Autodesk Fusion 360 part; units mm, degrees
(part 3 of 3)
ref_plane "WorkPlane3" through (-15.5, 0, 0) normal (1, 0, 0) x (0, 1, 0) in component "InnerFinger"
sketch "HW_M3x30_P1_0" plane through (-15.5, 0, 0) normal (1, 0, 0) x (0, 0, -1) in component "InnerFinger"
  circle A0 centre (-131.2077, -95.2377) radius 2.75
extrude "HW_M3x30_P1_0 (1)" add sketch "HW_M3x30_P1_0" along normal blind 3 separate body makes body 20 in component "InnerFinger"
ref_plane "WorkPlane4" through (-12.5, 0, 0) normal (1, 0, 0) x (0, 1, 0) in component "InnerFinger"
sketch "HW_M3x30_P1_1" plane through (-12.5, 0, 0) normal (1, 0, 0) x (0, 0, -1) in component "InnerFinger"
  circle A0 centre (-131.2077, -95.2377) radius 1.45
extrude "HW_M3x30_P1_1 (1)" add sketch "HW_M3x30_P1_1" along normal blind 30 bodies 20 in component "InnerFinger"
ref_plane "WorkPlane5" through (12.5, 0, 0) normal (1, 0, 0) x (0, 1, 0) in component "InnerFinger"
sketch "HW_M3x30_P1_2" plane through (12.5, 0, 0) normal (1, 0, 0) x (0, 0, -1) in component "InnerFinger"
  circle A0 centre (-131.2077, -95.2377) radius 3.2
extrude "HW_M3x30_P1_2 (1)" add sketch "HW_M3x30_P1_2" along normal blind 4 bodies 20 in component "InnerFinger"
sketch "HW_M3x30_P1_3" plane through (-12.5, 0, 0) normal (1, 0, 0) x (0, 0, -1) in component "InnerFinger"
  circle A0 centre (-131.2077, -95.2377) radius 3.5
extrude "HW_M3x30_P1_3 (1)" add sketch "HW_M3x30_P1_3" along normal blind 0.5 bodies 20 in component "InnerFinger"
ref_plane "WorkPlane6" through (12, 0, 0) normal (1, 0, 0) x (0, 1, 0) in component "InnerFinger"
sketch "HW_M3x30_P1_4" plane through (12, 0, 0) normal (1, 0, 0) x (0, 0, -1) in component "InnerFinger"
  circle A0 centre (-131.2077, -95.2377) radius 3.5
extrude "HW_M3x30_P1_4 (1)" add sketch "HW_M3x30_P1_4" along normal blind 0.5 bodies 20 in component "InnerFinger"
sketch "HW_M3x30_P2_0" plane through (-15.5, 0, 0) normal (1, 0, 0) x (0, 0, -1) in component "InnerFinger"
  circle A0 centre (-137.7227, -77.3367) radius 2.75
extrude "HW_M3x30_P2_0 (1)" add sketch "HW_M3x30_P2_0" along normal blind 3 separate body makes body 21 in component "InnerFinger"
sketch "HW_M3x30_P2_1" plane through (-12.5, 0, 0) normal (1, 0, 0) x (0, 0, -1) in component "InnerFinger"
  circle A0 centre (-137.7227, -77.3367) radius 1.45
extrude "HW_M3x30_P2_1 (1)" add sketch "HW_M3x30_P2_1" along normal blind 30 bodies 21 in component "InnerFinger"
sketch "HW_M3x30_P2_2" plane through (12.5, 0, 0) normal (1, 0, 0) x (0, 0, -1) in component "InnerFinger"
  circle A0 centre (-137.7227, -77.3367) radius 3.2
extrude "HW_M3x30_P2_2 (1)" add sketch "HW_M3x30_P2_2" along normal blind 4 bodies 21 in component "InnerFinger"
sketch "HW_M3x30_P2_3" plane through (-12.5, 0, 0) normal (1, 0, 0) x (0, 0, -1) in component "InnerFinger"
  circle A0 centre (-137.7227, -77.3367) radius 3.5
extrude "HW_M3x30_P2_3 (1)" add sketch "HW_M3x30_P2_3" along normal blind 0.5 bodies 21 in component "InnerFinger"
sketch "HW_M3x30_P2_4" plane through (12, 0, 0) normal (1, 0, 0) x (0, 0, -1) in component "InnerFinger"
  circle A0 centre (-137.7227, -77.3367) radius 3.5
extrude "HW_M3x30_P2_4 (1)" add sketch "HW_M3x30_P2_4" along normal blind 0.5 bodies 21 in component "InnerFinger"
ref_plane "WorkPlane2" through (25, 0, 0) normal (1, 0, 0) x (0, 1, 0) in component "Rod"
sketch "HW_M3x12_PinK_0" plane through (25, 0, 0) normal (1, 0, 0) x (0, 0, -1) in component "Rod"
  circle A0 centre (-55.2636, -29.6145) radius 2.75
extrude "HW_M3x12_PinK_0 (1)" add sketch "HW_M3x12_PinK_0" along normal blind 3 separate body makes body 22 in component "Rod"
ref_plane "WorkPlane3" through (13, 0, 0) normal (1, 0, 0) x (0, 1, 0) in component "Rod"
sketch "HW_M3x12_PinK_1" plane through (13, 0, 0) normal (1, 0, 0) x (0, 0, -1) in component "Rod"
  circle A0 centre (-55.2636, -29.6145) radius 1.45
extrude "HW_M3x12_PinK_1 (1)" add sketch "HW_M3x12_PinK_1" along normal blind 12 bodies 22 in component "Rod"
ref_plane "WorkPlane4" through (15, 0, 0) normal (1, 0, 0) x (0, 1, 0) in component "Rod"
sketch "HW_M3x12_PinK_2" plane through (15, 0, 0) normal (1, 0, 0) x (0, 0, -1) in component "Rod"
  circle A0 centre (-55.2636, -29.6145) radius 2.75
extrude "HW_M3x12_PinK_2 (1)" add sketch "HW_M3x12_PinK_2" along normal blind 4 bodies 22 in component "Rod"
ref_plane "WorkPlane5" through (24.5, 0, 0) normal (1, 0, 0) x (0, 1, 0) in component "Rod"
sketch "HW_M3x12_PinK_3" plane through (24.5, 0, 0) normal (1, 0, 0) x (0, 0, -1) in component "Rod"
  circle A0 centre (-55.2636, -29.6145) radius 3.5
extrude "HW_M3x12_PinK_3 (1)" add sketch "HW_M3x12_PinK_3" along normal blind 0.5 bodies 22 in component "Rod"
ref_plane "WorkPlane6" through (19, 0, 0) normal (1, 0, 0) x (0, 1, 0) in component "Rod"
sketch "HW_M3x12_PinK_4" plane through (19, 0, 0) normal (1, 0, 0) x (0, 0, -1) in component "Rod"
  circle A0 centre (-55.2636, -29.6145) radius 3.5
extrude "HW_M3x12_PinK_4 (1)" add sketch "HW_M3x12_PinK_4" along normal blind 0.5 bodies 22 in component "Rod"
ref_plane "WorkPlane2" through (11, 0, 0) normal (1, 0, 0) x (0, 1, 0) in component "Crank"
sketch "HW_M3x16_PinC_0" plane through (11, 0, 0) normal (1, 0, 0) x (0, 0, -1) in component "Crank"
  circle A0 centre (-11.5519, -29.5521) radius 2.75
extrude "HW_M3x16_PinC_0 (1)" add sketch "HW_M3x16_PinC_0" along normal blind 3 separate body makes body 23 in component "Crank"
ref_plane "WorkPlane3" through (14, 0, 0) normal (1, 0, 0) x (0, 1, 0) in component "Crank"
sketch "HW_M3x16_PinC_1" plane through (14, 0, 0) normal (1, 0, 0) x (0, 0, -1) in component "Crank"
  circle A0 centre (-11.5519, -29.5521) radius 1.45
extrude "HW_M3x16_PinC_1 (1)" add sketch "HW_M3x16_PinC_1" along normal blind 16 bodies 23 in component "Crank"
ref_plane "WorkPlane4" through (25, 0, 0) normal (1, 0, 0) x (0, 1, 0) in component "Crank"
sketch "HW_M3x16_PinC_2" plane through (25, 0, 0) normal (1, 0, 0) x (0, 0, -1) in component "Crank"
  circle A0 centre (-11.5519, -29.5521) radius 3.2
extrude "HW_M3x16_PinC_2 (1)" add sketch "HW_M3x16_PinC_2" along normal blind 4 bodies 23 in component "Crank"
ref_plane "WorkPlane5" through (24.5, 0, 0) normal (1, 0, 0) x (0, 1, 0) in component "Crank"
sketch "HW_M3x16_PinC_3" plane through (24.5, 0, 0) normal (1, 0, 0) x (0, 0, -1) in component "Crank"
  circle A0 centre (-11.5519, -29.5521) radius 3.5
extrude "HW_M3x16_PinC_3 (1)" add sketch "HW_M3x16_PinC_3" along normal blind 0.5 bodies 23 in component "Crank"
ref_plane "WorkPlane6" through (19, 0, 0) normal (1, 0, 0) x (0, 1, 0) in component "Crank"
sketch "HW_M3x16_PinC_4" plane through (19, 0, 0) normal (1, 0, 0) x (0, 0, -1) in component "Crank"
  circle A0 centre (-11.5519, -29.5521) radius 3.5
extrude "HW_M3x16_PinC_4 (1)" add sketch "HW_M3x16_PinC_4" along normal blind 0.5 bodies 23 in component "Crank"
ref_plane "WorkPlane10" through (-7.7, 0, 0) normal (1, 0, 0) x (0, 1, 0) in component "HousingBox"
ref_plane "WorkPlane11" through (-4.7, 0, 0) normal (1, 0, 0) x (0, 1, 0) in component "HousingBox"
ref_plane "WorkPlane12" through (3.5, 0, 0) normal (1, 0, 0) x (0, 1, 0) in component "HousingBox"
ref_plane "WorkPlane13" through (4, 0, 0) normal (1, 0, 0) x (0, 1, 0) in component "HousingBox"
ref_plane "WorkPlane22" through (0, 0, 40) normal (0, 0, 1) x (1, 0, 0) in component "Tower"
ref_plane "WorkPlane23" through (0, 0, 28) normal (0, 0, 1) x (1, 0, 0) in component "Tower"
ref_plane "WorkPlane24" through (0, 0, 29.6) normal (0, 0, 1) x (1, 0, 0) in component "Tower"
ref_plane "WorkPlane14" through (0, 0, 4) normal (0, 0, 1) x (1, 0, 0) in component "HousingBox"
ref_plane "WorkPlane15" through (0, 0, -8) normal (0, 0, 1) x (1, 0, 0) in component "HousingBox"
ref_plane "WorkPlane16" through (0, 0, -7.6) normal (0, 0, 1) x (1, 0, 0) in component "HousingBox"
ref_plane "WorkPlane6" through (0, 0, -9) normal (0, 0, 1) x (1, 0, 0) in component "SpacerB"
ref_plane "WorkPlane7" through (0, 0, -84) normal (0, 0, 1) x (1, 0, 0) in component "SpacerB"
ref_plane "WorkPlane4" through (0, 0, -79.7) normal (0, 0, 1) x (1, 0, 0) in component "CameraMount"
sketch "HW_M3x8_Camera0_0" plane through (0, 0, -79.7) normal (0, 0, 1) x (1, 0, 0) in component "CameraMount"
  circle A0 centre (100.36, 22.41) radius 2.75
extrude "HW_M3x8_Camera0_0 (1)" add sketch "HW_M3x8_Camera0_0" along normal blind 3 separate body makes body 24 in component "CameraMount"
ref_plane "WorkPlane5" through (0, 0, -76.7) normal (0, 0, 1) x (1, 0, 0) in component "CameraMount"
sketch "HW_M3x8_Camera0_1" plane through (0, 0, -76.7) normal (0, 0, 1) x (1, 0, 0) in component "CameraMount"
  circle A0 centre (100.36, 22.41) radius 1.45
extrude "HW_M3x8_Camera0_1 (1)" add sketch "HW_M3x8_Camera0_1" along normal blind 8 bodies 24 in component "CameraMount"
sketch "HW_M3x8_Camera1_0" plane through (0, 0, -79.7) normal (0, 0, 1) x (1, 0, 0) in component "CameraMount"
  circle A0 centre (100.36, -22.59) radius 2.75
extrude "HW_M3x8_Camera1_0 (1)" add sketch "HW_M3x8_Camera1_0" along normal blind 3 separate body makes body 25 in component "CameraMount"
sketch "HW_M3x8_Camera1_1" plane through (0, 0, -76.7) normal (0, 0, 1) x (1, 0, 0) in component "CameraMount"
  circle A0 centre (100.36, -22.59) radius 1.45
extrude "HW_M3x8_Camera1_1 (1)" add sketch "HW_M3x8_Camera1_1" along normal blind 8 bodies 25 in component "CameraMount"
ref_plane "WorkPlane7" through (0, -86.3377, 0) normal (0, 1, 0) x (0, 0, 1) in component "InnerFinger"
sketch "HW_M3x16_Pad0_0" plane through (0, -86.3377, 0) normal (0, 1, 0) x (1, 0, 0) in component "InnerFinger"
  circle A0 centre (0, -151.2077) radius 2.75
extrude "HW_M3x16_Pad0_0 (1)" add sketch "HW_M3x16_Pad0_0" along normal blind 3 separate body makes body 26 in component "InnerFinger"
ref_plane "WorkPlane8" through (0, -83.3377, 0) normal (0, 1, 0) x (0, 0, 1) in component "InnerFinger"
sketch "HW_M3x16_Pad0_1" plane through (0, -83.3377, 0) normal (0, 1, 0) x (1, 0, 0) in component "InnerFinger"
  circle A0 centre (0, -151.2077) radius 1.45
extrude "HW_M3x16_Pad0_1 (1)" add sketch "HW_M3x16_Pad0_1" along normal blind 16 bodies 26 in component "InnerFinger"
ref_plane "WorkPlane9" through (0, -71.3377, 0) normal (0, 1, 0) x (0, 0, 1) in component "InnerFinger"
sketch "HW_M3x16_Pad0_2" plane through (0, -71.3377, 0) normal (0, 1, 0) x (1, 0, 0) in component "InnerFinger"
  line L0 (2.75, -152.7954) -> (0, -154.3831)
  line L1 (0, -154.3831) -> (-2.75, -152.7954)
  line L2 (-2.75, -152.7954) -> (-2.75, -149.62)
  line L3 (-2.75, -149.62) -> (0, -148.0323)
  line L4 (0, -148.0323) -> (2.75, -149.62)
  line L5 (2.75, -149.62) -> (2.75, -152.7954)
extrude "HW_M3x16_Pad0_2 (1)" add sketch "HW_M3x16_Pad0_2" along normal blind 4 bodies 26 in component "InnerFinger"
sketch "HW_M3x16_Pad1_0" plane through (0, -86.3377, 0) normal (0, 1, 0) x (1, 0, 0) in component "InnerFinger"
  circle A0 centre (0, -165.2077) radius 2.75
extrude "HW_M3x16_Pad1_0 (1)" add sketch "HW_M3x16_Pad1_0" along normal blind 3 separate body makes body 27 in component "InnerFinger"
sketch "HW_M3x16_Pad1_1" plane through (0, -83.3377, 0) normal (0, 1, 0) x (1, 0, 0) in component "InnerFinger"
  circle A0 centre (0, -165.2077) radius 1.45
extrude "HW_M3x16_Pad1_1 (1)" add sketch "HW_M3x16_Pad1_1" along normal blind 16 bodies 27 in component "InnerFinger"
sketch "HW_M3x16_Pad1_2" plane through (0, -71.3377, 0) normal (0, 1, 0) x (1, 0, 0) in component "InnerFinger"
  line L0 (2.75, -166.7954) -> (0, -168.3831)
  line L1 (0, -168.3831) -> (-2.75, -166.7954)
  line L2 (-2.75, -166.7954) -> (-2.75, -163.62)
  line L3 (-2.75, -163.62) -> (0, -162.0323)
  line L4 (0, -162.0323) -> (2.75, -163.62)
  line L5 (2.75, -163.62) -> (2.75, -166.7954)
extrude "HW_M3x16_Pad1_2 (1)" add sketch "HW_M3x16_Pad1_2" along normal blind 4 bodies 27 in component "InnerFinger"
ref_plane "WorkPlane4" through (-4.8, 0, 0) normal (1, 0, 0) x (0, 1, 0) in component "Servo_D5545GS"
sketch "X03_cut_circle (3)" plane through (-4.8, 0, 0) normal (1, 0, 0) x (0, 0, -1) in component "Servo_D5545GS"
  circle A0 centre (-12.55, -28.7988) radius 2.25
extrude "X03_cut_circle (1)''" cut sketch "X03_cut_circle (3)" along normal blind 3.4 bodies 3 in component "Servo_D5545GS"
sketch "X04_cut_circle (2)" plane through (-4.8, 0, 0) normal (1, 0, 0) x (0, 0, -1) in component "Servo_D5545GS"
  circle A0 centre (-22.45, -28.7988) radius 2.25
extrude "X04_cut_circle (1)'" cut sketch "X04_cut_circle (2)" along normal blind 3.4 bodies 3 in component "Servo_D5545GS"
sketch "X05_cut_circle (4)" plane through (-4.8, 0, 0) normal (1, 0, 0) x (0, 0, -1) in component "Servo_D5545GS"
  circle A0 centre (-12.55, 19.8012) radius 2.25
extrude "X05_cut_circle (1)'''" cut sketch "X05_cut_circle (4)" along normal blind 3.4 bodies 3 in component "Servo_D5545GS"
sketch "X06_cut_circle (4)" plane through (-4.8, 0, 0) normal (1, 0, 0) x (0, 0, -1) in component "Servo_D5545GS"
  circle A0 centre (-22.45, 19.8012) radius 2.25
extrude "X06_cut_circle (1)'''" cut sketch "X06_cut_circle (4)" along normal blind 3.4 bodies 3 in component "Servo_D5545GS"
ref_plane "WorkPlane2" through (0, 0, -72.3) normal (0, 0, 1) x (1, 0, 0) in component "RealSense_D435i_Ref"
sketch "Z01_cut_circle (2)" plane through (0, 0, -72.3) normal (0, 0, 1) x (1, 0, 0) in component "RealSense_D435i_Ref"
  circle A0 centre (100.36, 22.41) radius 1.25
extrude "Z01_cut_circle (1)'" cut sketch "Z01_cut_circle (2)" along normal blind 5.1 bodies 15 in component "RealSense_D435i_Ref"
sketch "Z02_cut_circle (3)" plane through (0, 0, -72.3) normal (0, 0, 1) x (1, 0, 0) in component "RealSense_D435i_Ref"
  circle A0 centre (100.36, -22.59) radius 1.25
extrude "Z02_cut_circle (1)''" cut sketch "Z02_cut_circle (3)" along normal blind 5.1 bodies 15 in component "RealSense_D435i_Ref"
ref_plane "WorkPlane10" through (-7.6, 0, 0) normal (1, 0, 0) x (0, 1, 0) in component "InnerFinger"
sketch "X04_cut_rect" plane through (-7.6, 0, 0) normal (1, 0, 0) x (0, 0, -1) in component "InnerFinger"
  line L0 (-121.2077, -71.3377) -> (-121.2077, -69.2377)
  line L1 (-121.2077, -69.2377) -> (-181.2077, -69.2377)
  line L2 (-181.2077, -69.2377) -> (-181.2077, -71.3377)
  line L3 (-181.2077, -71.3377) -> (-121.2077, -71.3377)
extrude "X04_cut_rect (1)" cut sketch "X04_cut_rect" along normal blind 15.2 bodies 10 in component "InnerFinger"
ref_plane "WorkPlane17" through (4, 0, 0) normal (1, 0, 0) x (0, 1, 0) in component "HousingBox"
sketch "HW_M3x16_ServoEar0_0" plane through (4, 0, 0) normal (1, 0, 0) x (0, 0, -1) in component "HousingBox"
  circle A0 centre (-12.55, -28.7988) radius 2.75
extrude "HW_M3x16_ServoEar0_0 (1)" add sketch "HW_M3x16_ServoEar0_0" along normal blind 3 separate body makes body 28 in component "HousingBox"
ref_plane "WorkPlane18" through (3.5, 0, 0) normal (1, 0, 0) x (0, 1, 0) in component "HousingBox"
sketch "HW_M3x16_ServoEar0_1" plane through (3.5, 0, 0) normal (1, 0, 0) x (0, 0, -1) in component "HousingBox"
  circle A0 centre (-12.55, -28.7988) radius 3.5
extrude "HW_M3x16_ServoEar0_1 (1)" add sketch "HW_M3x16_ServoEar0_1" along normal blind 0.5 bodies 28 in component "HousingBox"
ref_plane "WorkPlane19" through (-12, 0, 0) normal (1, 0, 0) x (0, 1, 0) in component "HousingBox"
sketch "HW_M3x16_ServoEar0_2" plane through (-12, 0, 0) normal (1, 0, 0) x (0, 0, -1) in component "HousingBox"
  circle A0 centre (-12.55, -28.7988) radius 1.45
extrude "HW_M3x16_ServoEar0_2 (1)" add sketch "HW_M3x16_ServoEar0_2" along normal blind 16 bodies 28 in component "HousingBox"
ref_plane "WorkPlane20" through (-5.2, 0, 0) normal (1, 0, 0) x (0, 1, 0) in component "HousingBox"
sketch "HW_M3x16_ServoEar0_3" plane through (-5.2, 0, 0) normal (1, 0, 0) x (0, 0, -1) in component "HousingBox"
  circle A0 centre (-12.55, -28.7988) radius 3.5
extrude "HW_M3x16_ServoEar0_3 (1)" add sketch "HW_M3x16_ServoEar0_3" along normal blind 0.5 bodies 28 in component "HousingBox"
ref_plane "WorkPlane21" through (-9.2, 0, 0) normal (1, 0, 0) x (0, 1, 0) in component "HousingBox"
sketch "HW_M3x16_ServoEar0_4" plane through (-9.2, 0, 0) normal (1, 0, 0) x (0, 0, -1) in component "HousingBox"
  line L0 (-14.1377, -26.0488) -> (-15.7254, -28.7988)
  line L1 (-15.7254, -28.7988) -> (-14.1377, -31.5488)
  line L2 (-14.1377, -31.5488) -> (-10.9623, -31.5488)
  line L3 (-10.9623, -31.5488) -> (-9.3746, -28.7988)
  line L4 (-9.3746, -28.7988) -> (-10.9623, -26.0488)
  line L5 (-10.9623, -26.0488) -> (-14.1377, -26.0488)
extrude "HW_M3x16_ServoEar0_4 (1)" add sketch "HW_M3x16_ServoEar0_4" along normal blind 4 bodies 28 in component "HousingBox"
sketch "HW_M3x16_ServoEar1_0" plane through (4, 0, 0) normal (1, 0, 0) x (0, 0, -1) in component "HousingBox"
  circle A0 centre (-22.45, -28.7988) radius 2.75
extrude "HW_M3x16_ServoEar1_0 (1)" add sketch "HW_M3x16_ServoEar1_0" along normal blind 3 separate body makes body 29 in component "HousingBox"
sketch "HW_M3x16_ServoEar1_1" plane through (3.5, 0, 0) normal (1, 0, 0) x (0, 0, -1) in component "HousingBox"
  circle A0 centre (-22.45, -28.7988) radius 3.5
extrude "HW_M3x16_ServoEar1_1 (1)" add sketch "HW_M3x16_ServoEar1_1" along normal blind 0.5 bodies 29 in component "HousingBox"
sketch "HW_M3x16_ServoEar1_2" plane through (-12, 0, 0) normal (1, 0, 0) x (0, 0, -1) in component "HousingBox"
  circle A0 centre (-22.45, -28.7988) radius 1.45
extrude "HW_M3x16_ServoEar1_2 (1)" add sketch "HW_M3x16_ServoEar1_2" along normal blind 16 bodies 29 in component "HousingBox"
sketch "HW_M3x16_ServoEar1_3" plane through (-5.2, 0, 0) normal (1, 0, 0) x (0, 0, -1) in component "HousingBox"
  circle A0 centre (-22.45, -28.7988) radius 3.5
extrude "HW_M3x16_ServoEar1_3 (1)" add sketch "HW_M3x16_ServoEar1_3" along normal blind 0.5 bodies 29 in component "HousingBox"
sketch "HW_M3x16_ServoEar1_4" plane through (-9.2, 0, 0) normal (1, 0, 0) x (0, 0, -1) in component "HousingBox"
  line L0 (-24.0377, -26.0488) -> (-25.6254, -28.7988)
  line L1 (-25.6254, -28.7988) -> (-24.0377, -31.5488)
  line L2 (-24.0377, -31.5488) -> (-20.8623, -31.5488)
  line L3 (-20.8623, -31.5488) -> (-19.2746, -28.7988)
  line L4 (-19.2746, -28.7988) -> (-20.8623, -26.0488)
  line L5 (-20.8623, -26.0488) -> (-24.0377, -26.0488)
extrude "HW_M3x16_ServoEar1_4 (1)" add sketch "HW_M3x16_ServoEar1_4" along normal blind 4 bodies 29 in component "HousingBox"
sketch "HW_M3x16_ServoEar2_0" plane through (4, 0, 0) normal (1, 0, 0) x (0, 0, -1) in component "HousingBox"
  circle A0 centre (-12.55, 19.8012) radius 2.75
extrude "HW_M3x16_ServoEar2_0 (1)" add sketch "HW_M3x16_ServoEar2_0" along normal blind 3 separate body makes body 30 in component "HousingBox"
sketch "HW_M3x16_ServoEar2_1" plane through (3.5, 0, 0) normal (1, 0, 0) x (0, 0, -1) in component "HousingBox"
  circle A0 centre (-12.55, 19.8012) radius 3.5
extrude "HW_M3x16_ServoEar2_1 (1)" add sketch "HW_M3x16_ServoEar2_1" along normal blind 0.5 bodies 30 in component "HousingBox"
sketch "HW_M3x16_ServoEar2_2" plane through (-12, 0, 0) normal (1, 0, 0) x (0, 0, -1) in component "HousingBox"
  circle A0 centre (-12.55, 19.8012) radius 1.45
extrude "HW_M3x16_ServoEar2_2 (1)" add sketch "HW_M3x16_ServoEar2_2" along normal blind 16 bodies 30 in component "HousingBox"
sketch "HW_M3x16_ServoEar2_3" plane through (-5.2, 0, 0) normal (1, 0, 0) x (0, 0, -1) in component "HousingBox"
  circle A0 centre (-12.55, 19.8012) radius 3.5
extrude "HW_M3x16_ServoEar2_3 (1)" add sketch "HW_M3x16_ServoEar2_3" along normal blind 0.5 bodies 30 in component "HousingBox"
sketch "HW_M3x16_ServoEar2_4" plane through (-9.2, 0, 0) normal (1, 0, 0) x (0, 0, -1) in component "HousingBox"
  line L0 (-14.1377, 22.5512) -> (-15.7254, 19.8012)
  line L1 (-15.7254, 19.8012) -> (-14.1377, 17.0512)
  line L2 (-14.1377, 17.0512) -> (-10.9623, 17.0512)
  line L3 (-10.9623, 17.0512) -> (-9.3746, 19.8012)
  line L4 (-9.3746, 19.8012) -> (-10.9623, 22.5512)
  line L5 (-10.9623, 22.5512) -> (-14.1377, 22.5512)
extrude "HW_M3x16_ServoEar2_4 (1)" add sketch "HW_M3x16_ServoEar2_4" along normal blind 4 bodies 30 in component "HousingBox"
sketch "HW_M3x16_ServoEar3_0" plane through (4, 0, 0) normal (1, 0, 0) x (0, 0, -1) in component "HousingBox"
  circle A0 centre (-22.45, 19.8012) radius 2.75
extrude "HW_M3x16_ServoEar3_0 (1)" add sketch "HW_M3x16_ServoEar3_0" along normal blind 3 separate body makes body 31 in component "HousingBox"
sketch "HW_M3x16_ServoEar3_1" plane through (3.5, 0, 0) normal (1, 0, 0) x (0, 0, -1) in component "HousingBox"
  circle A0 centre (-22.45, 19.8012) radius 3.5
extrude "HW_M3x16_ServoEar3_1 (1)" add sketch "HW_M3x16_ServoEar3_1" along normal blind 0.5 bodies 31 in component "HousingBox"
sketch "HW_M3x16_ServoEar3_2" plane through (-12, 0, 0) normal (1, 0, 0) x (0, 0, -1) in component "HousingBox"
  circle A0 centre (-22.45, 19.8012) radius 1.45
extrude "HW_M3x16_ServoEar3_2 (1)" add sketch "HW_M3x16_ServoEar3_2" along normal blind 16 bodies 31 in component "HousingBox"
sketch "HW_M3x16_ServoEar3_3" plane through (-5.2, 0, 0) normal (1, 0, 0) x (0, 0, -1) in component "HousingBox"
  circle A0 centre (-22.45, 19.8012) radius 3.5
extrude "HW_M3x16_ServoEar3_3 (1)" add sketch "HW_M3x16_ServoEar3_3" along normal blind 0.5 bodies 31 in component "HousingBox"
sketch "HW_M3x16_ServoEar3_4" plane through (-9.2, 0, 0) normal (1, 0, 0) x (0, 0, -1) in component "HousingBox"
  line L0 (-24.0377, 22.5512) -> (-25.6254, 19.8012)
  line L1 (-25.6254, 19.8012) -> (-24.0377, 17.0512)
  line L2 (-24.0377, 17.0512) -> (-20.8623, 17.0512)
  line L3 (-20.8623, 17.0512) -> (-19.2746, 19.8012)
  line L4 (-19.2746, 19.8012) -> (-20.8623, 22.5512)
  line L5 (-20.8623, 22.5512) -> (-24.0377, 22.5512)
extrude "HW_M3x16_ServoEar3_4 (1)" add sketch "HW_M3x16_ServoEar3_4" along normal blind 4 bodies 31 in component "HousingBox"
ref_plane "WorkPlane25" through (0, 0, 40) normal (0, 0, 1) x (1, 0, 0) in component "Tower"
sketch "HW_M3x12_Tower0_0" plane through (0, 0, 40) normal (0, 0, 1) x (1, 0, 0) in component "Tower"
  circle A0 centre (-29, -31) radius 2.75
extrude "HW_M3x12_Tower0_0 (1)" add sketch "HW_M3x12_Tower0_0" along normal blind 3 separate body makes body 32 in component "Tower"
ref_plane "WorkPlane26" through (0, 0, 28) normal (0, 0, 1) x (1, 0, 0) in component "Tower"
sketch "HW_M3x12_Tower0_1" plane through (0, 0, 28) normal (0, 0, 1) x (1, 0, 0) in component "Tower"
  circle A0 centre (-29, -31) radius 1.45
extrude "HW_M3x12_Tower0_1 (1)" add sketch "HW_M3x12_Tower0_1" along normal blind 12 bodies 32 in component "Tower"
ref_plane "WorkPlane27" through (0, 0, 29.6) normal (0, 0, 1) x (1, 0, 0) in component "Tower"
sketch "HW_M3x12_Tower0_2" plane through (0, 0, 29.6) normal (0, 0, 1) x (1, 0, 0) in component "Tower"
  line L0 (-28.2808, -27.9071) -> (-31.3189, -28.8307)
  line L1 (-31.3189, -28.8307) -> (-32.0381, -31.9236)
  line L2 (-32.0381, -31.9236) -> (-29.7192, -34.0929)
  line L3 (-29.7192, -34.0929) -> (-26.6811, -33.1693)
  line L4 (-26.6811, -33.1693) -> (-25.9619, -30.0764)
  line L5 (-25.9619, -30.0764) -> (-28.2808, -27.9071)
extrude "HW_M3x12_Tower0_2 (1)" add sketch "HW_M3x12_Tower0_2" along normal blind 4 bodies 32 in component "Tower"
sketch "HW_M3x12_Tower1_0" plane through (0, 0, 40) normal (0, 0, 1) x (1, 0, 0) in component "Tower"
  circle A0 centre (-29, 31) radius 2.75
extrude "HW_M3x12_Tower1_0 (1)" add sketch "HW_M3x12_Tower1_0" along normal blind 3 separate body makes body 33 in component "Tower"
sketch "HW_M3x12_Tower1_1" plane through (0, 0, 28) normal (0, 0, 1) x (1, 0, 0) in component "Tower"
  circle A0 centre (-29, 31) radius 1.45
extrude "HW_M3x12_Tower1_1 (1)" add sketch "HW_M3x12_Tower1_1" along normal blind 12 bodies 33 in component "Tower"
sketch "HW_M3x12_Tower1_2" plane through (0, 0, 29.6) normal (0, 0, 1) x (1, 0, 0) in component "Tower"
  line L0 (-25.9619, 30.0764) -> (-26.6811, 33.1693)
  line L1 (-26.6811, 33.1693) -> (-29.7192, 34.0929)
  line L2 (-29.7192, 34.0929) -> (-32.0381, 31.9236)
  line L3 (-32.0381, 31.9236) -> (-31.3189, 28.8307)
  line L4 (-31.3189, 28.8307) -> (-28.2808, 27.9071)
  line L5 (-28.2808, 27.9071) -> (-25.9619, 30.0764)
extrude "HW_M3x12_Tower1_2 (1)" add sketch "HW_M3x12_Tower1_2" along normal blind 4 bodies 33 in component "Tower"
sketch "HW_M3x12_Tower2_0" plane through (0, 0, 40) normal (0, 0, 1) x (1, 0, 0) in component "Tower"
  circle A0 centre (27, 31) radius 2.75
extrude "HW_M3x12_Tower2_0 (1)" add sketch "HW_M3x12_Tower2_0" along normal blind 3 separate body makes body 34 in component "Tower"
sketch "HW_M3x12_Tower2_1" plane through (0, 0, 28) normal (0, 0, 1) x (1, 0, 0) in component "Tower"
  circle A0 centre (27, 31) radius 1.45
extrude "HW_M3x12_Tower2_1 (1)" add sketch "HW_M3x12_Tower2_1" along normal blind 12 bodies 34 in component "Tower"
sketch "HW_M3x12_Tower2_2" plane through (0, 0, 29.6) normal (0, 0, 1) x (1, 0, 0) in component "Tower"
  line L0 (26.3911, 27.8835) -> (29.3945, 28.9144)
  line L1 (29.3945, 28.9144) -> (30.0034, 32.0309)
  line L2 (30.0034, 32.0309) -> (27.6089, 34.1165)
  line L3 (27.6089, 34.1165) -> (24.6055, 33.0856)
  line L4 (24.6055, 33.0856) -> (23.9966, 29.9691)
  line L5 (23.9966, 29.9691) -> (26.3911, 27.8835)
extrude "HW_M3x12_Tower2_2 (1)" add sketch "HW_M3x12_Tower2_2" along normal blind 4 bodies 34 in component "Tower"
sketch "HW_M3x12_Tower3_0" plane through (0, 0, 40) normal (0, 0, 1) x (1, 0, 0) in component "Tower"
  circle A0 centre (27, -10) radius 2.75
extrude "HW_M3x12_Tower3_0 (1)" add sketch "HW_M3x12_Tower3_0" along normal blind 3 separate body makes body 35 in component "Tower"
sketch "HW_M3x12_Tower3_1" plane through (0, 0, 28) normal (0, 0, 1) x (1, 0, 0) in component "Tower"
  circle A0 centre (27, -10) radius 1.45
extrude "HW_M3x12_Tower3_1 (1)" add sketch "HW_M3x12_Tower3_1" along normal blind 12 bodies 35 in component "Tower"
sketch "HW_M3x12_Tower3_2" plane through (0, 0, 29.6) normal (0, 0, 1) x (1, 0, 0) in component "Tower"
  line L0 (23.8698, -10.5338) -> (25.8971, -12.9778)
  line L1 (25.8971, -12.9778) -> (29.0274, -12.444)
  line L2 (29.0274, -12.444) -> (30.1302, -9.4662)
  line L3 (30.1302, -9.4662) -> (28.1029, -7.0222)
  line L4 (28.1029, -7.0222) -> (24.9726, -7.556)
  line L5 (24.9726, -7.556) -> (23.8698, -10.5338)
extrude "HW_M3x12_Tower3_2 (1)" add sketch "HW_M3x12_Tower3_2" along normal blind 4 bodies 35 in component "Tower"
ref_plane "WorkPlane22" through (0, 0, 4) normal (0, 0, 1) x (1, 0, 0) in component "HousingBox"
sketch "HW_M3x12_Base0_0" plane through (0, 0, 4) normal (0, 0, 1) x (1, 0, 0) in component "HousingBox"
  circle A0 centre (26.8, 11.1) radius 2.75
extrude "HW_M3x12_Base0_0 (1)" add sketch "HW_M3x12_Base0_0" along normal blind 3 separate body makes body 36 in component "HousingBox"
ref_plane "WorkPlane23" through (0, 0, -8) normal (0, 0, 1) x (1, 0, 0) in component "HousingBox"
sketch "HW_M3x12_Base0_1" plane through (0, 0, -8) normal (0, 0, 1) x (1, 0, 0) in component "HousingBox"
  circle A0 centre (26.8, 11.1) radius 1.45
extrude "HW_M3x12_Base0_1 (1)" add sketch "HW_M3x12_Base0_1" along normal blind 12 bodies 36 in component "HousingBox"
ref_plane "WorkPlane24" through (0, 0, -7.6) normal (0, 0, 1) x (1, 0, 0) in component "HousingBox"
sketch "HW_M3x12_Base0_2" plane through (0, 0, -7.6) normal (0, 0, 1) x (1, 0, 0) in component "HousingBox"
  line L0 (28.7332, 13.6192) -> (25.5849, 14.0337)
  line L1 (25.5849, 14.0337) -> (23.6518, 11.5146)
  line L2 (23.6518, 11.5146) -> (24.8668, 8.5808)
  line L3 (24.8668, 8.5808) -> (28.0151, 8.1663)
  line L4 (28.0151, 8.1663) -> (29.9482, 10.6854)
  line L5 (29.9482, 10.6854) -> (28.7332, 13.6192)
extrude "HW_M3x12_Base0_2 (1)" add sketch "HW_M3x12_Base0_2" along normal blind 4 bodies 36 in component "HousingBox"
sketch "HW_M3x12_Base1_0" plane through (0, 0, 4) normal (0, 0, 1) x (1, 0, 0) in component "HousingBox"
  circle A0 centre (-11.1, 26.8) radius 2.75
extrude "HW_M3x12_Base1_0 (1)" add sketch "HW_M3x12_Base1_0" along normal blind 3 separate body makes body 37 in component "HousingBox"
sketch "HW_M3x12_Base1_1" plane through (0, 0, -8) normal (0, 0, 1) x (1, 0, 0) in component "HousingBox"
  circle A0 centre (-11.1, 26.8) radius 1.45
extrude "HW_M3x12_Base1_1 (1)" add sketch "HW_M3x12_Base1_1" along normal blind 12 bodies 37 in component "HousingBox"
sketch "HW_M3x12_Base1_2" plane through (0, 0, -7.6) normal (0, 0, 1) x (1, 0, 0) in component "HousingBox"
  line L0 (-13.6192, 28.7332) -> (-14.0337, 25.5849)
  line L1 (-14.0337, 25.5849) -> (-11.5146, 23.6518)
  line L2 (-11.5146, 23.6518) -> (-8.5808, 24.8668)
  line L3 (-8.5808, 24.8668) -> (-8.1663, 28.0151)
  line L4 (-8.1663, 28.0151) -> (-10.6854, 29.9482)
  line L5 (-10.6854, 29.9482) -> (-13.6192, 28.7332)
extrude "HW_M3x12_Base1_2 (1)" add sketch "HW_M3x12_Base1_2" along normal blind 4 bodies 37 in component "HousingBox"
sketch "HW_M3x12_Base2_0" plane through (0, 0, 4) normal (0, 0, 1) x (1, 0, 0) in component "HousingBox"
  circle A0 centre (-18, -28.5) radius 2.75
extrude "HW_M3x12_Base2_0 (1)" add sketch "HW_M3x12_Base2_0" along normal blind 3 separate body makes body 38 in component "HousingBox"
sketch "HW_M3x12_Base2_1" plane through (0, 0, -8) normal (0, 0, 1) x (1, 0, 0) in component "HousingBox"
  circle A0 centre (-18, -28.5) radius 1.45
extrude "HW_M3x12_Base2_1 (1)" add sketch "HW_M3x12_Base2_1" along normal blind 12 bodies 38 in component "HousingBox"
sketch "HW_M3x12_Base2_2" plane through (0, 0, -7.6) normal (0, 0, 1) x (1, 0, 0) in component "HousingBox"
  line L0 (-18.1261, -31.6729) -> (-15.3152, -30.1957)
  line L1 (-15.3152, -30.1957) -> (-15.1891, -27.0227)
  line L2 (-15.1891, -27.0227) -> (-17.8739, -25.3271)
  line L3 (-17.8739, -25.3271) -> (-20.6848, -26.8043)
  line L4 (-20.6848, -26.8043) -> (-20.8109, -29.9773)
  line L5 (-20.8109, -29.9773) -> (-18.1261, -31.6729)
extrude "HW_M3x12_Base2_2 (1)" add sketch "HW_M3x12_Base2_2" along normal blind 4 bodies 38 in component "HousingBox"
sketch "HW_M3x12_Base3_0" plane through (0, 0, 4) normal (0, 0, 1) x (1, 0, 0) in component "HousingBox"
  circle A0 centre (11.1, -26.8) radius 2.75
extrude "HW_M3x12_Base3_0 (1)" add sketch "HW_M3x12_Base3_0" along normal blind 3 separate body makes body 39 in component "HousingBox"
sketch "HW_M3x12_Base3_1" plane through (0, 0, -8) normal (0, 0, 1) x (1, 0, 0) in component "HousingBox"
  circle A0 centre (11.1, -26.8) radius 1.45
extrude "HW_M3x12_Base3_1 (1)" add sketch "HW_M3x12_Base3_1" along normal blind 12 bodies 39 in component "HousingBox"
sketch "HW_M3x12_Base3_2" plane through (0, 0, -7.6) normal (0, 0, 1) x (1, 0, 0) in component "HousingBox"
  line L0 (13.6192, -28.7332) -> (14.0337, -25.5849)
  line L1 (14.0337, -25.5849) -> (11.5146, -23.6518)
  line L2 (11.5146, -23.6518) -> (8.5808, -24.8668)
  line L3 (8.5808, -24.8668) -> (8.1663, -28.0151)
  line L4 (8.1663, -28.0151) -> (10.6854, -29.9482)
  line L5 (10.6854, -29.9482) -> (13.6192, -28.7332)
extrude "HW_M3x12_Base3_2 (1)" add sketch "HW_M3x12_Base3_2" along normal blind 4 bodies 39 in component "HousingBox"
ref_plane "WorkPlane3" through (0, 0, -72.3) normal (0, 0, 1) x (1, 0, 0) in component "RealSense_D435i_Ref"
sketch "Z03_cut_circle (5)" plane through (0, 0, -72.3) normal (0, 0, 1) x (1, 0, 0) in component "RealSense_D435i_Ref"
  circle A0 centre (100.36, 22.41) radius 1.5
extrude "Z03_cut_circle (1)''''" cut sketch "Z03_cut_circle (5)" along normal blind 5.1 bodies 15 in component "RealSense_D435i_Ref"
sketch "Z04_cut_circle (4)" plane through (0, 0, -72.3) normal (0, 0, 1) x (1, 0, 0) in component "RealSense_D435i_Ref"
  circle A0 centre (100.36, -22.59) radius 1.5
extrude "Z04_cut_circle (1)'''" cut sketch "Z04_cut_circle (4)" along normal blind 5.1 bodies 15 in component "RealSense_D435i_Ref"
ref_plane "WorkPlane11" through (11.5, 0, 0) normal (1, 0, 0) x (0, 1, 0) in component "InnerKnuckle"
sketch "X00_add_hull (5)" plane through (11.5, 0, 0) normal (1, 0, 0) x (0, 0, -1) in component "InnerKnuckle"
  line L0 (-96.896, -51.2707) -> (-57.2186, -17.6597)
  arc A0 (-57.2186, -17.6597) -> (-65.6214, -7.7403) centre (-61.42, -12.7) ccw
  line L1 (-65.6214, -7.7403) -> (-105.2988, -41.3514)
  arc A1 (-105.2988, -41.3514) -> (-96.896, -51.2707) centre (-101.0974, -46.3111) ccw
extrude "X00_add_hull (1)''''" add sketch "X00_add_hull (5)" along normal blind 7.5 separate body makes body 40 in component "InnerKnuckle"
ref_plane "WorkPlane12" through (-19, 0, 0) normal (1, 0, 0) x (0, 1, 0) in component "InnerKnuckle"
sketch "X01_add_hull (4)" plane through (-19, 0, 0) normal (1, 0, 0) x (0, 0, -1) in component "InnerKnuckle"
  line L0 (-96.896, -51.2707) -> (-57.2186, -17.6597)
  arc A0 (-57.2186, -17.6597) -> (-65.6214, -7.7403) centre (-61.42, -12.7) ccw
  line L1 (-65.6214, -7.7403) -> (-105.2988, -41.3514)
  arc A1 (-105.2988, -41.3514) -> (-96.896, -51.2707) centre (-101.0974, -46.3111) ccw
extrude "X01_add_hull (1)'''" add sketch "X01_add_hull (4)" along normal blind 7.5 bodies 40 makes body 41 in component "InnerKnuckle"
sketch "X02_add_hull" plane through (11.5, 0, 0) normal (1, 0, 0) x (0, 0, -1) in component "InnerKnuckle"
  line L0 (-49.9988, -28.0234) -> (-55.1979, -10.8196)
  arc A0 (-55.1979, -10.8196) -> (-67.3951, -15.259) centre (-61.42, -12.7) ccw
  line L1 (-67.3951, -15.259) -> (-60.3195, -31.7798)
  arc A1 (-60.3195, -31.7798) -> (-49.9988, -28.0234) centre (-55.2636, -29.6145) ccw
extrude "X02_add_hull (1)" add sketch "X02_add_hull" along normal blind 7.5 bodies 40 41 in component "InnerKnuckle"
sketch "X03_add_hull" plane through (-19, 0, 0) normal (1, 0, 0) x (0, 0, -1) in component "InnerKnuckle"
  line L0 (-95.37, -49.978) -> (-89.2658, -44.8071)
  arc A0 (-89.2658, -44.8071) -> (-97.6685, -34.8877) centre (-93.4671, -39.8474) ccw
  line L1 (-97.6685, -34.8877) -> (-103.7727, -40.0587)
  arc A1 (-103.7727, -40.0587) -> (-95.37, -49.978) centre (-99.5714, -45.0183) ccw
extrude "X03_add_hull (1)" add sketch "X03_add_hull" along normal blind 38 bodies 40 41 in component "InnerKnuckle"
ref_plane "WorkPlane13" through (-12, 0, 0) normal (1, 0, 0) x (0, 1, 0) in component "InnerKnuckle"
sketch "X04_add_hull" plane through (-12, 0, 0) normal (1, 0, 0) x (0, 0, -1) in component "InnerKnuckle"
  line L0 (-133.5213, -82.2963) -> (-89.2658, -44.8071)
  arc A0 (-89.2658, -44.8071) -> (-97.6685, -34.8877) centre (-93.4671, -39.8474) ccw
  line L1 (-97.6685, -34.8877) -> (-141.9241, -72.377)
  arc A1 (-141.9241, -72.377) -> (-133.5213, -82.2963) centre (-137.7227, -77.3367) ccw
extrude "X04_add_hull (1)" add sketch "X04_add_hull" along normal blind 24 bodies 40 in component "InnerKnuckle"
ref_plane "WorkPlane14" through (-7.75, 0, 0) normal (1, 0, 0) x (0, 1, 0) in component "InnerKnuckle"
sketch "X05_cut_hull" plane through (-7.75, 0, 0) normal (1, 0, 0) x (0, 0, -1) in component "InnerKnuckle"
  line L0 (-132.0455, -83.3914) -> (-124.776, -76.5752)
  arc A0 (-124.776, -76.5752) -> (-134.8501, -64.6898) centre (-130.1112, -70.8852) ccw
  line L1 (-134.8501, -64.6898) -> (-142.7653, -70.7441)
  arc A1 (-142.7653, -70.7441) -> (-132.0455, -83.3914) centre (-137.7227, -77.3367) ccw
extrude "X05_cut_hull (1)" cut sketch "X05_cut_hull" along normal blind 15.5 bodies 40 in component "InnerKnuckle"
sketch "X06_cut_circle (5)" plane through (-19, 0, 0) normal (1, 0, 0) x (0, 0, -1) in component "InnerKnuckle"
  circle A0 centre (-61.42, -12.7) radius 1.65
extrude "X06_cut_circle (1)''''" cut sketch "X06_cut_circle (5)" along normal blind 38 bodies 40 in component "InnerKnuckle"
sketch "X07_cut_circle (5)" plane through (-12, 0, 0) normal (1, 0, 0) x (0, 0, -1) in component "InnerKnuckle"
  circle A0 centre (-137.7227, -77.3367) radius 1.65
extrude "X07_cut_circle (1)''''" cut sketch "X07_cut_circle (5)" along normal blind 24 bodies 40 in component "InnerKnuckle"
sketch "X08_cut_circle (3)" plane through (11.5, 0, 0) normal (1, 0, 0) x (0, 0, -1) in component "InnerKnuckle"
  circle A0 centre (-55.2636, -29.6145) radius 1.7
extrude "X08_cut_circle (1)''" cut sketch "X08_cut_circle (3)" along normal blind 7.5 bodies 40 in component "InnerKnuckle"
ref_plane "WorkPlane15" through (14.8, 0, 0) normal (1, 0, 0) x (0, 1, 0) in component "InnerKnuckle"
sketch "X09_cut_hex" plane through (14.8, 0, 0) normal (1, 0, 0) x (0, 0, -1) in component "InnerKnuckle"
  line L0 (-56.9091, -26.7645) -> (-58.5545, -29.6145)
  line L1 (-58.5545, -29.6145) -> (-56.9091, -32.4645)
  line L2 (-56.9091, -32.4645) -> (-53.6182, -32.4645)
  line L3 (-53.6182, -32.4645) -> (-51.9727, -29.6145)
  line L4 (-51.9727, -29.6145) -> (-53.6182, -26.7645)
  line L5 (-53.6182, -26.7645) -> (-56.9091, -26.7645)
extrude "X09_cut_hex (1)" cut sketch "X09_cut_hex" along normal blind 4.2 bodies 40 in component "InnerKnuckle"
ref_plane "WorkPlane8" through (0, 0, -14) normal (0, 0, 1) x (1, 0, 0) in component "SpacerB"
sketch "Z40_cut_circle" plane through (0, 0, -14) normal (0, 0, 1) x (1, 0, 0) in component "SpacerB"
  circle A0 centre (23.097, -9.5671) radius 5.5
extrude "Z40_cut_circle (1)" cut sketch "Z40_cut_circle" along normal blind 5.1 bodies 12 in component "SpacerB"
sketch "Z41_cut_circle" plane through (0, 0, -14) normal (0, 0, 1) x (1, 0, 0) in component "SpacerB"
  circle A0 centre (9.5671, 23.097) radius 5.5
extrude "Z41_cut_circle (1)" cut sketch "Z41_cut_circle" along normal blind 5.1 bodies 12 in component "SpacerB"
sketch "Z42_cut_circle" plane through (0, 0, -14) normal (0, 0, 1) x (1, 0, 0) in component "SpacerB"
  circle A0 centre (-23.097, 9.5671) radius 5.5
extrude "Z42_cut_circle (1)" cut sketch "Z42_cut_circle" along normal blind 5.1 bodies 12 in component "SpacerB"
sketch "Z43_cut_circle" plane through (0, 0, -14) normal (0, 0, 1) x (1, 0, 0) in component "SpacerB"
  circle A0 centre (-9.5671, -23.097) radius 5.5
extrude "Z43_cut_circle (1)" cut sketch "Z43_cut_circle" along normal blind 5.1 bodies 12 in component "SpacerB"
ref_plane "WorkPlane28" through (-22.5, 0, 0) normal (1, 0, 0) x (0, 1, 0) in component "Tower"
sketch "HW_M3x50_PivotI_L_0" plane through (-22.5, 0, 0) normal (1, 0, 0) x (0, 0, -1) in component "Tower"
  circle A0 centre (-61.42, -12.7) radius 2.75
extrude "HW_M3x50_PivotI_L_0 (1)" add sketch "HW_M3x50_PivotI_L_0" along normal blind 3 separate body makes body 42 in component "Tower"
ref_plane "WorkPlane29" through (-19.5, 0, 0) normal (1, 0, 0) x (0, 1, 0) in component "Tower"
sketch "HW_M3x50_PivotI_L_1" plane through (-19.5, 0, 0) normal (1, 0, 0) x (0, 0, -1) in component "Tower"
  circle A0 centre (-61.42, -12.7) radius 1.45
extrude "HW_M3x50_PivotI_L_1 (1)" add sketch "HW_M3x50_PivotI_L_1" along normal blind 50 bodies 42 in component "Tower"
ref_plane "WorkPlane30" through (19.5, 0, 0) normal (1, 0, 0) x (0, 1, 0) in component "Tower"
sketch "HW_M3x50_PivotI_L_2" plane through (19.5, 0, 0) normal (1, 0, 0) x (0, 0, -1) in component "Tower"
  circle A0 centre (-61.42, -12.7) radius 3.2
extrude "HW_M3x50_PivotI_L_2 (1)" add sketch "HW_M3x50_PivotI_L_2" along normal blind 4 bodies 42 in component "Tower"
sketch "HW_M3x50_PivotI_L_3" plane through (-19.5, 0, 0) normal (1, 0, 0) x (0, 0, -1) in component "Tower"
  circle A0 centre (-61.42, -12.7) radius 3.5
extrude "HW_M3x50_PivotI_L_3 (1)" add sketch "HW_M3x50_PivotI_L_3" along normal blind 0.5 bodies 42 in component "Tower"
ref_plane "WorkPlane31" through (19, 0, 0) normal (1, 0, 0) x (0, 1, 0) in component "Tower"
sketch "HW_M3x50_PivotI_L_4" plane through (19, 0, 0) normal (1, 0, 0) x (0, 0, -1) in component "Tower"
  circle A0 centre (-61.42, -12.7) radius 3.5
extrude "HW_M3x50_PivotI_L_4 (1)" add sketch "HW_M3x50_PivotI_L_4" along normal blind 0.5 bodies 42 in component "Tower"
ref_plane "WorkPlane32" through (-11.5, 0, 0) normal (1, 0, 0) x (0, 1, 0) in component "Tower"
sketch "HW_M3x50_PivotI_L_5" plane through (-11.5, 0, 0) normal (1, 0, 0) x (0, 0, -1) in component "Tower"
  circle A0 centre (-61.42, -12.7) radius 3.5
extrude "HW_M3x50_PivotI_L_5 (1)" add sketch "HW_M3x50_PivotI_L_5" along normal blind 0.5 bodies 42 in component "Tower"
ref_plane "WorkPlane33" through (11, 0, 0) normal (1, 0, 0) x (0, 1, 0) in component "Tower"
sketch "HW_M3x50_PivotI_L_6" plane through (11, 0, 0) normal (1, 0, 0) x (0, 0, -1) in component "Tower"
  circle A0 centre (-61.42, -12.7) radius 3.5
extrude "HW_M3x50_PivotI_L_6 (1)" add sketch "HW_M3x50_PivotI_L_6" along normal blind 0.5 bodies 42 in component "Tower"
sketch "HW_M3x50_PivotI_R_0" plane through (19.5, 0, 0) normal (1, 0, 0) x (0, 0, -1) in component "Tower"
  circle A0 centre (-61.42, 12.7) radius 2.75
extrude "HW_M3x50_PivotI_R_0 (1)" add sketch "HW_M3x50_PivotI_R_0" along normal blind 3 separate body makes body 43 in component "Tower"
ref_plane "WorkPlane34" through (-30.5, 0, 0) normal (1, 0, 0) x (0, 1, 0) in component "Tower"
sketch "HW_M3x50_PivotI_R_1" plane through (-30.5, 0, 0) normal (1, 0, 0) x (0, 0, -1) in component "Tower"
  circle A0 centre (-61.42, 12.7) radius 1.45
extrude "HW_M3x50_PivotI_R_1 (1)" add sketch "HW_M3x50_PivotI_R_1" along normal blind 50 bodies 43 in component "Tower"
ref_plane "WorkPlane35" through (-23.5, 0, 0) normal (1, 0, 0) x (0, 1, 0) in component "Tower"
sketch "HW_M3x50_PivotI_R_2" plane through (-23.5, 0, 0) normal (1, 0, 0) x (0, 0, -1) in component "Tower"
  circle A0 centre (-61.42, 12.7) radius 3.2
extrude "HW_M3x50_PivotI_R_2 (1)" add sketch "HW_M3x50_PivotI_R_2" along normal blind 4 bodies 43 in component "Tower"
sketch "HW_M3x50_PivotI_R_3" plane through (19, 0, 0) normal (1, 0, 0) x (0, 0, -1) in component "Tower"
  circle A0 centre (-61.42, 12.7) radius 3.5
extrude "HW_M3x50_PivotI_R_3 (1)" add sketch "HW_M3x50_PivotI_R_3" along normal blind 0.5 bodies 43 in component "Tower"
sketch "HW_M3x50_PivotI_R_4" plane through (-19.5, 0, 0) normal (1, 0, 0) x (0, 0, -1) in component "Tower"
  circle A0 centre (-61.42, 12.7) radius 3.5
extrude "HW_M3x50_PivotI_R_4 (1)" add sketch "HW_M3x50_PivotI_R_4" along normal blind 0.5 bodies 43 in component "Tower"
sketch "HW_M3x50_PivotI_R_5" plane through (11, 0, 0) normal (1, 0, 0) x (0, 0, -1) in component "Tower"
  circle A0 centre (-61.42, 12.7) radius 3.5
extrude "HW_M3x50_PivotI_R_5 (1)" add sketch "HW_M3x50_PivotI_R_5" along normal blind 0.5 bodies 43 in component "Tower"
sketch "HW_M3x50_PivotI_R_6" plane through (-11.5, 0, 0) normal (1, 0, 0) x (0, 0, -1) in component "Tower"
  circle A0 centre (-61.42, 12.7) radius 3.5
extrude "HW_M3x50_PivotI_R_6 (1)" add sketch "HW_M3x50_PivotI_R_6" along normal blind 0.5 bodies 43 in component "Tower"
sketch "HW_M6x70_Flange0_0" plane through (0, 0, -14) normal (0, 0, 1) x (1, 0, 0) in component "SpacerB"
  circle A0 centre (23.097, -9.5671) radius 5
extrude "HW_M6x70_Flange0_0 (1)" add sketch "HW_M6x70_Flange0_0" along normal blind 6 separate body makes body 44 in component "SpacerB"
ref_plane "WorkPlane9" through (0, 0, -84) normal (0, 0, 1) x (1, 0, 0) in component "SpacerB"
sketch "HW_M6x70_Flange0_1" plane through (0, 0, -84) normal (0, 0, 1) x (1, 0, 0) in component "SpacerB"
  circle A0 centre (23.097, -9.5671) radius 2.95
extrude "HW_M6x70_Flange0_1 (1)" add sketch "HW_M6x70_Flange0_1" along normal blind 70 bodies 44 in component "SpacerB"
sketch "HW_M6x70_Flange1_0" plane through (0, 0, -14) normal (0, 0, 1) x (1, 0, 0) in component "SpacerB"
  circle A0 centre (9.5671, 23.097) radius 5
extrude "HW_M6x70_Flange1_0 (1)" add sketch "HW_M6x70_Flange1_0" along normal blind 6 separate body makes body 45 in component "SpacerB"
sketch "HW_M6x70_Flange1_1" plane through (0, 0, -84) normal (0, 0, 1) x (1, 0, 0) in component "SpacerB"
  circle A0 centre (9.5671, 23.097) radius 2.95
extrude "HW_M6x70_Flange1_1 (1)" add sketch "HW_M6x70_Flange1_1" along normal blind 70 bodies 45 in component "SpacerB"
sketch "HW_M6x70_Flange2_0" plane through (0, 0, -14) normal (0, 0, 1) x (1, 0, 0) in component "SpacerB"
  circle A0 centre (-23.097, 9.5671) radius 5
extrude "HW_M6x70_Flange2_0 (1)" add sketch "HW_M6x70_Flange2_0" along normal blind 6 separate body makes body 46 in component "SpacerB"
sketch "HW_M6x70_Flange2_1" plane through (0, 0, -84) normal (0, 0, 1) x (1, 0, 0) in component "SpacerB"
  circle A0 centre (-23.097, 9.5671) radius 2.95
extrude "HW_M6x70_Flange2_1 (1)" add sketch "HW_M6x70_Flange2_1" along normal blind 70 bodies 46 in component "SpacerB"
sketch "HW_M6x70_Flange3_0" plane through (0, 0, -14) normal (0, 0, 1) x (1, 0, 0) in component "SpacerB"
  circle A0 centre (-9.5671, -23.097) radius 5
extrude "HW_M6x70_Flange3_0 (1)" add sketch "HW_M6x70_Flange3_0" along normal blind 6 separate body makes body 47 in component "SpacerB"
sketch "HW_M6x70_Flange3_1" plane through (0, 0, -84) normal (0, 0, 1) x (1, 0, 0) in component "SpacerB"
  circle A0 centre (-9.5671, -23.097) radius 2.95
extrude "HW_M6x70_Flange3_1 (1)" add sketch "HW_M6x70_Flange3_1" along normal blind 70 bodies 47 in component "SpacerB"
component "Tower" placed x (1, 0, 0) y (0, 1, 0) z (0, 0, 1) at (0, 0, 0)
component "HousingBox" placed x (1, 0, 0) y (0, 1, 0) z (0, 0, 1) at (0, 0, 0)
component "Servo_D5545GS" placed x (1, 0, 0) y (0, 1, 0) z (0, 0, 1) at (0, 0, 0)
component "ServoHorn_Ref" placed x (1, 0, 0) y (0, 1, 0) z (0, 0, 1) at (0, 0, 0)
component "Crank" placed x (1, 0, 0) y (0, 1, 0) z (0, 0, 1) at (0, 0, 0)
component "Rod" placed x (1, 0, 0) y (0, 1, 0) z (0, 0, 1) at (0, 0, 0)
component "OuterKnuckle_L" placed x (1, 0, 0) y (0, 1, 0) z (0, 0, 1) at (0, 0, 0)
component "OuterKnuckle_R" placed x (-1, 0, 0) y (0, -1, 0) z (0, 0, 1) at (0, 0, 0)
component "OuterFinger" placed x (1, 0, 0) y (0, 1, 0) z (0, 0, 1) at (0, 0, 0)
component "InnerKnuckle" placed x (1, 0, 0) y (0, 1, 0) z (0, 0, 1) at (0, 0, 0)
component "InnerFinger" placed x (1, 0, 0) y (0, 1, 0) z (0, 0, 1) at (0, 0, 0)
component "Fingertip" placed x (1, 0, 0) y (0, 1, 0) z (0, 0, 1) at (0, 0, 0)
component "SpacerB" placed x (1, 0, 0) y (0, 1, 0) z (0, 0, 1) at (0, 0, 0)
component "SpacerA" placed x (1, 0, 0) y (0, 1, 0) z (0, 0, 1) at (0, 0, 0)
component "CameraMount" placed x (1, 0, 0) y (0, 1, 0) z (0, 0, 1) at (0, 0, 0)
component "RealSense_D435i_Ref" placed x (1, 0, 0) y (0, 1, 0) z (0, 0, 1) at (0, 0, 0)
component "OuterFinger" placed x (-1, 0, 0) y (0, -1, 0) z (0, 0, 1) at (0, 0, 0)
component "InnerKnuckle" placed x (-1, 0, 0) y (0, -1, 0) z (0, 0, 1) at (0, 0, 0)
component "InnerFinger" placed x (-1, 0, 0) y (0, -1, 0) z (0, 0, 1) at (0, 0, 0)
component "Fingertip" placed x (-1, 0, 0) y (0, -1, 0) z (0, 0, 1) at (0, 0, 0)
named bodies: "Tower", "HousingBox", "Servo_D5545GS", "ServoHorn_Ref", "Crank", "Rod", "OuterKnuckle_L", "OuterKnuckle_R", "OuterFinger", "InnerFinger", "Fingertip", "SpacerB", "SpacerA", "CameraMount", "RealSense_D435i_Ref", "HW_M3x30_PivotO_L", "HW_M3x30_PivotO_R", "HW_M3x30_J", "HW_M3x30_J2", "HW_M3x30_P1", "HW_M3x30_P2", "HW_M3x12_PinK", "HW_M3x16_PinC", "HW_M3x8_Camera0", "HW_M3x8_Camera1", "HW_M3x16_Pad0", "HW_M3x16_Pad1", "HW_M3x16_ServoEar0", "HW_M3x16_ServoEar1", "HW_M3x16_ServoEar2", "HW_M3x16_ServoEar3", "HW_M3x12_Tower0", "HW_M3x12_Tower1", "HW_M3x12_Tower2", "HW_M3x12_Tower3", "HW_M3x12_Base0", "HW_M3x12_Base1", "HW_M3x12_Base2", "HW_M3x12_Base3", "InnerKnuckle", "InnerKnuckle_frag1_1", "HW_M3x50_PivotI_L", "HW_M3x50_PivotI_R", "HW_M6x70_Flange0", "HW_M6x70_Flange1", "HW_M6x70_Flange2", "HW_M6x70_Flange3"
